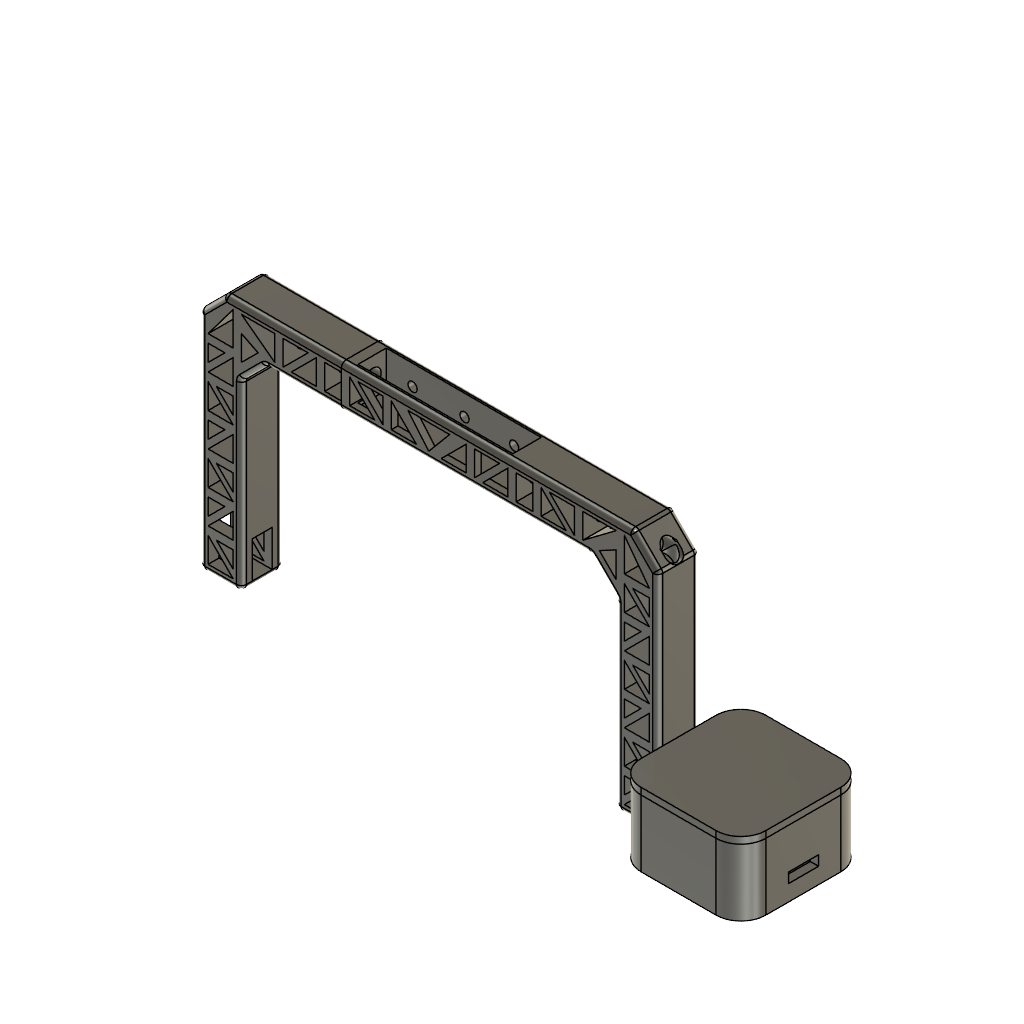
Gaslands Gate (Autodesk Fusion 360 design; units mm, degrees)
Autodesk Fusion 360 part; units mm, degrees
sketch "Sketch1" plane through (0, 0, 0) normal (0, 1, 0) x (1, 0, 0)
  line L0 (0, 0) -> (25, 0)
  line L1 (25, 0) -> (25, -125)
  line L2 (25, -125) -> (250, -125)
  line L3 (250, -125) -> (250, 0)
  line L4 (250, 0) -> (275, 0)
  line L5 (275, 0) -> (275, -150)
  line L6 (275, -150) -> (0, -150)
  line L7 (0, -150) -> (0, 0)
  line L8 (25, -110) -> (40, -125)
  line L9 (250, -110) -> (235, -125)
  line L10 (275, -135) -> (260, -150)
  line L11 (0, -135) -> (15, -150)
  dimension "d1" = 25
  constraint coincident L0.start L7.end
  constraint horizontal L0
  constraint perpendicular L0 L1
  constraint perpendicular L1 L2
  constraint perpendicular L2 L3
  constraint perpendicular L1 L4
  constraint perpendicular L4 L5
  constraint perpendicular L5 L6
  constraint perpendicular L0 L7
  constraint coincident L1 L8.start
  constraint coincident L2 L8.end
  constraint coincident L3 L9.start
  constraint coincident L2 L9.end
  constraint perpendicular L8 L9
  constraint coincident L5 L10.start
  constraint coincident L6 L10.end
  constraint parallel L9 L10
  constraint coincident L7 L11.start
  constraint coincident L6 L11.end
  constraint perpendicular L10 L11
  measures "d1" distance of L3.end L4.end
extrude "Extrude1" add sketch "Sketch1" along normal blind 25 contours L0 L1 L2 L3 L4 L5 L6 L7 L10 L11 | L1 L2 L8 | L2 L3 L9 makes body 1
fillet "Fillet1" radius 3 28 edges at (0, 12.5, 135) (32.5, 25, 117.5) (250, 0, 55) (137.5, 0, 150) (235, 12.5, 125) (250, 12.5, 110) (0, 0, 67.5) (137.5, 0, 125) (25, 25, 55) (40, 12.5, 125) (250, 25, 55) (242.5, 25, 117.5) (137.5, 25, 150) (275, 0, 67.5) (260, 12.5, 150) (242.5, 0, 117.5) (7.5, 0, 142.5) (0, 25, 67.5) (267.5, 25, 142.5) (275, 25, 67.5) (275, 12.5, 135) (25, 0, 55) (32.5, 0, 117.5) (25, 12.5, 110) (267.5, 0, 142.5) (137.5, 25, 125) (7.5, 25, 142.5) (15, 12.5, 150) 12 faces at (170, 0, 141.6667) (250, 8.3333, 73.3333) (170, 25, 141.6667) (275, 8.3333, 45) (0, 8.3333, 90) (178.3333, 16.6667, 150) (270, 8.3333, 140) (5, 8.3333, 140) (105, 8.3333, 125) (245, 8.3333, 115) (25, 8.3333, 36.6667) (30, 8.3333, 115) on bodies 1
sketch "Sketch2" plane through (0, 0, 150) normal (0, 0, 1) x (-1, 0, 0)
  line L0 (-16.2426, -3) -> (-258.7574, -3)
  line L1 (-258.7574, -3) -> (-258.7574, -22)
  line L2 (-258.7574, -22) -> (-16.2426, -22)
  line L3 (-16.2426, -22) -> (-16.2426, -3)
  line L4 (-275, -50, -150) -> (-350, -50, -150)
  line L5 (-350, -50, -150) -> (-350, 25, -150)
  line L6 (-350, 25, -150) -> (-275, 25, -150)
  line L7 (-275, 25, -150) -> (-275, -50, -150)
extrude "Extrude2" add sketch "Sketch2" along normal blind 40 separate body contours L4 L5 L6 L7 in plane through (0, 0, 0) normal (0, 0, 1) makes body 2
sketch "Sketch3" plane through (0, 0, 40) normal (0, 0, 1) x (-1, 0, 0)
  line L0 (-275, 25) -> (-350, 25)
  line L1 (-350, 25) -> (-350, -50)
  line L2 (-350, -50) -> (-275, -50)
  line L3 (-275, -50) -> (-275, 25)
  line L4 (-280, -45) -> (-345, -45)
  line L5 (-345, -45) -> (-345, 20)
  line L6 (-345, 20) -> (-280, 20)
  line L7 (-280, 20) -> (-280, -45)
  constraint horizontal L4
  constraint vertical L5
  constraint horizontal L6
  constraint vertical L7
extrude "Extrude3" cut sketch "Sketch3" against normal blind 35 contours L4 L5 L6 L7 bodies 2 1
fillet "Fillet2" radius 15 8 edges at (280, 45, 22.5) (275, -25, 20) (350, -25, 20) (350, 50, 20) (345, -20, 22.5) (345, 45, 22.5) (280, -20, 22.5) (275, 50, 20) on bodies 2
sketch "Sketch4" plane through (250, 0, 0) normal (-1, 0, 0) x (0, -1, 0)
  line L0 (-3, 3) -> (-3, 108.7574)
  line L1 (-3, 108.7574) -> (-22, 108.7574)
  line L2 (-22, 108.7574) -> (-22, 3)
  line L3 (-22, 3) -> (-3, 3)
sketch "Sketch5" plane through (250, 0, 0) normal (-1, 0, 0) x (0, -1, 0)
  line L0 (-22, 7) -> (-18.5, 7) construction
  line L1 (-3, 7) -> (-6.5, 7) construction
  line L2 (-18.5, 3.0129) -> (-6.5, 3.0129)
  line L3 (-6.5, 3.0129) -> (-6.5, 25.0129)
  line L4 (-6.5, 25.0129) -> (-18.5, 25.0129)
  line L5 (-18.5, 25.0129) -> (-18.5, 3.0129)
  dimension "d13" = 3.5
  dimension "d14" = 3.5
  dimension "d15" = 12
  dimension "d16" = 22
  constraint horizontal L0
  constraint horizontal L1
  constraint horizontal L2
  constraint vertical L3
  constraint horizontal L4
  constraint vertical L5
  measures "d13" distance of L0.start L0.end
  measures "d14" distance of L1.start L1.end
  measures "d15" distance of L2.start L2.end
  measures "d16" distance of L2.start L4.end
extrude "Extrude4" cut sketch "Sketch5" against normal blind 50 bodies 2 1
sketch "Sketch6" plane through (25, 0, 0) normal (1, 0, 0) x (0, 1, 0)
  line L0 (3, 108.7574) -> (3, 3)
  line L1 (3, 3) -> (22, 3)
  line L2 (22, 3) -> (22, 108.7574)
  line L3 (22, 108.7574) -> (3, 108.7574)
  line L4 (3, 10) -> (6.5, 10) construction
  line L5 (22, 10) -> (18.5, 10) construction
  line L6 (6.5, 3) -> (18.5, 3)
  line L7 (18.5, 3) -> (18.5, 25)
  line L8 (18.5, 25) -> (6.5, 25)
  line L9 (6.5, 25) -> (6.5, 3)
  dimension "d19" = 3.5
  dimension "d20" = 3.5
  dimension "d21" = 12
  dimension "d22" = 22
  constraint coincident L0 L4.start
  constraint perpendicular L0 L4
  constraint coincident L2 L5.start
  constraint perpendicular L2 L5
  constraint horizontal L6
  constraint vertical L7
  constraint horizontal L8
  constraint vertical L9
  constraint coincident L1 L6.start
  measures "d19" distance of L4.start L4.end
  measures "d20" distance of L5.start L5.end
  measures "d21" distance of L6.start L6.end
  measures "d22" distance of L6.start L8.end
extrude "Extrude5" cut sketch "Sketch6" against normal blind 50 contours L1 L6 L7 L8 L9 bodies 1 2
sketch "Sketch7" plane through (0, 0, 150) normal (0, 0, 1) x (-1, 0, 0)
  line L0 (-16.2426, -3) -> (-258.7574, -3)
  line L1 (-258.7574, -3) -> (-258.7574, -22)
  line L2 (-258.7574, -22) -> (-16.2426, -22)
  line L3 (-16.2426, -22) -> (-16.2426, -3)
  line L4 (-16.2426, -12.5) -> (-91.2426, -12.5) construction
  line L5 (-258.7574, -12.5) -> (-183.7574, -12.5) construction
  line L6 (-184, -4) -> (-91, -4)
  line L7 (-91, -4) -> (-91, -21)
  line L8 (-91, -21) -> (-184, -21)
  line L9 (-184, -21) -> (-184, -4)
  dimension "d25" = 75
  dimension "d26" = 75
  constraint midpoint L3 L4.start
  constraint perpendicular L1 L4
  constraint midpoint L1 L5.start
  constraint perpendicular L1 L5
  constraint horizontal L6
  constraint vertical L7
  constraint horizontal L8
  constraint vertical L9
  measures "d25" distance of L4.start L4.end
  measures "d26" distance of L5.start L5.end
extrude "Extrude6" cut sketch "Sketch7" against normal blind 22 contours L6 L7 L8 L9 bodies 2 1
sketch "Sketch9" plane through (0, 21, 0) normal (0, -1, 0) x (1, 0, 0)
  line L0 (184, 150) -> (91, 150)
  line L1 (91, 150) -> (91, 128)
  line L2 (91, 128) -> (184, 128)
  line L3 (184, 128) -> (184, 150)
  circle A0 centre (137.9868, 137.5616) radius 2.75
  circle A1 centre (167.7904, 137.5616) radius 2.75
  circle A2 centre (106.797, 137.7349) radius 2.75
  dimension "d34" = 5.5
  dimension "d35" = 5.5
  dimension "d36" = 5.5
  measures "d34" diameter of A0
  measures "d35" diameter of A1
  measures "d36" diameter of A2
sketch "Sketch11" plane through (350, 0, 0) normal (1, 0, 0) x (0, 1, 0)
  line L0 (35, 0) -> (35, 40)
  line L1 (35, 40) -> (-10, 40)
  line L2 (-10, 40) -> (-10, 0)
  line L3 (-10, 0) -> (35, 0)
  line L4 (3.6168, 9.6364) -> (21.6168, 9.6364)
  line L5 (21.6168, 9.6364) -> (21.6168, 15.6364)
  line L6 (21.6168, 15.6364) -> (3.6168, 15.6364)
  line L7 (3.6168, 15.6364) -> (3.6168, 9.6364)
  dimension "d30" = 18
  dimension "d31" = 6
  constraint horizontal L4
  constraint vertical L5
  constraint horizontal L6
  constraint vertical L7
  measures "d30" distance of L4.start L4.end
  measures "d31" distance of L4.start L6.end
extrude "Extrude7" cut sketch "Sketch11" against normal blind 48 contours L4 L5 L6 L7 bodies 1 2
extrude "Extrude8" cut sketch "Sketch9" against normal blind 4 contours A0 | A1 | A2 bodies 1 2
hole "Hole1" at (184, 12.5, 139) direction (1, 0, 0) diameter 10 depth 104 tip angle 118 bodies 1 2
hole "Hole2" at (91, 12.9327, 138.6221) direction (-1, 0, 0) diameter 10 depth 95 tip angle 118 bodies 1 2
hole "Hole3" at (-2.2469, 12.2437, 25) direction (0, 0, 1) diameter 10 depth 145 tip angle 118 bodies 1
hole "Hole4" at (268.4842, 12.4358, 25.0129) direction (0, 0, 1) diameter 10 depth 116 tip angle 118 bodies 2 1
sketch "Sketch13" plane through (0, 0, 40) normal (0, 0, 1) x (-1, 0, 0)
  line L0 (-345, -30) -> (-345, 5)
  arc A0 (-330, 20) -> (-345, 5) centre (-330, 5) ccw
  line L1 (-330, 20) -> (-295, 20)
  arc A1 (-280, 5) -> (-295, 20) centre (-295, 5) ccw
  line L2 (-280, 5) -> (-280, -30)
  arc A2 (-295, -45) -> (-280, -30) centre (-295, -30) ccw
  line L3 (-295, -45) -> (-330, -45)
  arc A3 (-345, -30) -> (-330, -45) centre (-330, -30) ccw
  arc A4 (-290, -50) -> (-275, -35) centre (-290, -35) ccw
  line L4 (-275, -35) -> (-275, 10)
  arc A5 (-275, 10) -> (-290, 25) centre (-290, 10) ccw
  line L5 (-290, 25) -> (-335, 25)
  arc A6 (-335, 25) -> (-350, 10) centre (-335, 10) ccw
  line L6 (-350, 10) -> (-350, -35)
  arc A7 (-350, -35) -> (-335, -50) centre (-335, -35) ccw
  line L7 (-335, -50) -> (-290, -50)
  line L8 (-350, -50) -> (-275, -50)
  line L9 (-275, -50) -> (-275, 25)
  line L10 (-275, 25) -> (-350, 25)
  line L11 (-350, 25) -> (-350, -50)
  constraint horizontal L8
  constraint vertical L9
  constraint horizontal L10
  constraint vertical L11
extrude "Extrude9" add sketch "Sketch13" along normal blind 4 separate body contours L0 A0 L1 A1 L2 A2 L3 A3 | A4 L4 A5 L5 A6 L6 A7 L7 L8 L9 L10 L11 makes body 3
sketch "Sketch14" plane through (0, 0, 0) normal (0, -1, 0) x (1, 0, 0)
  line L0 (3, 133.7574) -> (3, 3)
  line L1 (3, 3) -> (22, 3)
  line L2 (22, 3) -> (22, 108.7574)
  arc A0 (23.7574, 113) -> (22, 108.7574) centre (28, 108.7574) ccw
  line L3 (23.7574, 113) -> (37, 126.2426)
  arc A1 (41.2426, 128) -> (37, 126.2426) centre (41.2426, 122) ccw
  line L4 (41.2426, 128) -> (233.7574, 128)
  arc A2 (238, 126.2426) -> (233.7574, 128) centre (233.7574, 122) ccw
  line L5 (238, 126.2426) -> (251.2426, 113)
  arc A3 (253, 108.7574) -> (251.2426, 113) centre (247, 108.7574) ccw
  line L6 (253, 108.7574) -> (253, 3)
  line L7 (253, 3) -> (272, 3)
  line L8 (272, 3) -> (272, 133.7574)
  line L9 (272, 133.7574) -> (258.7574, 147)
  line L10 (258.7574, 147) -> (16.2426, 147)
  line L11 (16.2426, 147) -> (3, 133.7574)
  line L12 (5, 5) -> (20, 5)
  line L13 (20, 5) -> (5, 20)
  line L14 (5, 20) -> (5, 5)
  line L15 (20, 10) -> (10, 20)
  line L16 (10, 20) -> (20, 20)
  line L17 (20, 10) -> (20, 20)
  line L18 (5, 25) -> (20, 25)
  line L19 (20, 25) -> (20, 40)
  line L20 (20, 40) -> (5, 25)
  line L21 (5, 30) -> (15, 40)
  line L22 (15, 40) -> (5, 40)
  line L23 (5, 40) -> (5, 30)
  line L24 (20, 45) -> (5, 45)
  line L25 (5, 45) -> (5, 60)
  line L26 (5, 60) -> (20, 45)
  line L27 (20, 50) -> (10, 60)
  line L28 (10, 60) -> (20, 60)
  line L29 (20, 60) -> (20, 50)
  line L30 (5, 65) -> (20, 65)
  line L31 (20, 65) -> (20, 80)
  line L32 (20, 80) -> (5, 65)
  line L33 (5, 80) -> (5, 70)
  line L34 (5, 70) -> (15, 80)
  line L35 (15, 80) -> (5, 80)
  line L36 (5, 85) -> (20, 85)
  line L37 (20, 85) -> (5, 100)
  line L38 (5, 100) -> (5, 85)
  line L39 (10, 100) -> (20, 90)
  line L40 (20, 90) -> (20, 100)
  line L41 (20, 100) -> (10, 100)
  line L42 (5, 105) -> (20, 105)
  line L43 (20, 105) -> (20, 120)
  line L44 (20, 120) -> (5, 105)
  line L45 (5, 110) -> (15, 120)
  line L46 (15, 120) -> (5, 120)
  line L47 (5, 120) -> (5, 110)
  line L48 (255, 5) -> (270, 5)
  line L49 (270, 5) -> (270, 20)
  line L50 (270, 20) -> (255, 5)
  line L51 (255, 10) -> (265, 20)
  line L52 (265, 20) -> (255, 20)
  line L53 (255, 20) -> (255, 10)
  line L54 (270, 25) -> (255, 25)
  line L55 (255, 25) -> (255, 40)
  line L56 (255, 40) -> (270, 25)
  line L57 (270, 30) -> (260, 40)
  line L58 (260, 40) -> (270, 40)
  line L59 (270, 40) -> (270, 30)
  line L60 (255, 45) -> (270, 45)
  line L61 (270, 45) -> (270, 60)
  line L62 (270, 60) -> (255, 45)
  line L63 (255, 50) -> (265, 60)
  line L64 (265, 60) -> (255, 60)
  line L65 (255, 60) -> (255, 50)
  line L66 (255, 65) -> (270, 65)
  line L67 (270, 65) -> (255, 80)
  line L68 (255, 80) -> (255, 65)
  line L69 (260, 80) -> (270, 70)
  line L70 (270, 70) -> (270, 80)
  line L71 (270, 80) -> (260, 80)
  line L72 (270, 85) -> (255, 85)
  line L73 (255, 85) -> (270, 100)
  line L74 (270, 100) -> (270, 85)
  line L75 (255, 90) -> (265, 100)
  line L76 (255, 90) -> (255, 100)
  line L77 (255, 100) -> (265, 100)
  line L78 (270, 105) -> (255, 105)
  line L79 (255, 105) -> (255, 120)
  line L80 (255, 120) -> (270, 105)
  line L81 (270, 110) -> (270, 120)
  line L82 (270, 120) -> (260, 120)
  line L83 (260, 120) -> (270, 110)
  line L84 (5, 125) -> (20, 145)
  line L85 (20, 145) -> (20, 125)
  line L86 (20, 125) -> (5, 125)
  line L87 (25, 120) -> (35, 130)
  line L88 (35, 130) -> (25, 135)
  line L89 (25, 135) -> (25, 120)
  line L90 (25, 145) -> (45, 145)
  line L91 (45, 145) -> (45, 130)
  line L92 (45, 130) -> (25, 145)
  line L93 (270, 125) -> (255, 125)
  line L94 (255, 125) -> (255, 145)
  line L95 (255, 145) -> (270, 125)
  line L96 (250, 145) -> (230, 130)
  line L97 (230, 130) -> (230, 145)
  line L98 (230, 145) -> (250, 145)
  line L99 (250, 135) -> (250, 119.6213)
  line L100 (250, 119.6213) -> (240, 129.6213)
  line L101 (240, 129.6213) -> (250, 135)
  line L102 (225, 130) -> (210, 145)
  line L103 (210, 145) -> (225, 145)
  line L104 (225, 145) -> (225, 130)
  line L105 (205, 145) -> (220, 130)
  line L106 (220, 130) -> (205, 130)
  line L107 (205, 130) -> (205, 145)
  line L108 (50, 145) -> (50, 130)
  line L109 (50, 130) -> (65, 145)
  line L110 (65, 145) -> (50, 145)
  line L111 (55, 130) -> (70, 145)
  line L112 (70, 145) -> (70, 130)
  line L113 (70, 130) -> (55, 130)
  line L114 (75, 145) -> (75, 130)
  line L115 (75, 130) -> (85, 130)
  line L116 (85, 130) -> (85, 145)
  line L117 (85, 145) -> (75, 145)
  line L118 (200, 130) -> (200, 145)
  line L119 (200, 145) -> (190, 145)
  line L120 (190, 145) -> (190, 130)
  line L121 (190, 130) -> (200, 130)
  constraint perpendicular L2 L12
  constraint perpendicular L12 L14
  constraint parallel L13 L15
  constraint perpendicular L2 L16
  constraint perpendicular L16 L17
  constraint perpendicular L2 L18
  constraint perpendicular L18 L19
  constraint parallel L20 L21
  constraint parallel L18 L22
  constraint perpendicular L22 L23
  constraint perpendicular L23 L24
  constraint perpendicular L24 L25
  constraint perpendicular L2 L28
  constraint perpendicular L24 L29
  constraint perpendicular L29 L30
  constraint perpendicular L30 L31
  constraint perpendicular L30 L33
  constraint parallel L32 L34
  constraint perpendicular L33 L35
  constraint parallel L35 L36
  constraint perpendicular L32 L37
  constraint perpendicular L36 L38
  constraint parallel L37 L39
  constraint parallel L38 L40
  constraint perpendicular L40 L41
  constraint perpendicular L40 L42
  constraint perpendicular L42 L43
  constraint parallel L44 L45
  constraint parallel L42 L46
  constraint perpendicular L46 L47
  constraint perpendicular L8 L48
  constraint perpendicular L48 L49
  constraint parallel L50 L51
  constraint parallel L48 L52
  constraint perpendicular L52 L53
  constraint perpendicular L49 L54
  constraint perpendicular L54 L55
  constraint parallel L56 L57
  constraint parallel L54 L58
  constraint perpendicular L58 L59
  constraint perpendicular L59 L60
  constraint perpendicular L58 L61
  constraint parallel L62 L63
  constraint perpendicular L6 L64
  constraint perpendicular L64 L65
  constraint perpendicular L65 L66
  constraint perpendicular L66 L68
  constraint parallel L67 L69
  constraint parallel L8 L70
  constraint perpendicular L70 L71
  constraint perpendicular L8 L72
  constraint perpendicular L72 L74
  constraint parallel L73 L75
  constraint vertical L76
  constraint perpendicular L76 L77
  constraint parallel L77 L78
  constraint perpendicular L78 L79
  constraint perpendicular L78 L81
  constraint perpendicular L81 L82
  constraint parallel L80 L83
  constraint perpendicular L10 L85
  constraint perpendicular L85 L86
  constraint parallel L85 L89
  constraint perpendicular L89 L90
  constraint perpendicular L90 L91
  constraint perpendicular L8 L93
  constraint perpendicular L93 L94
  constraint perpendicular L95 L96
  constraint parallel L94 L97
  constraint perpendicular L94 L98
  constraint perpendicular L98 L99
  constraint parallel L5 L100
  constraint parallel L100 L102
  constraint parallel L4 L103
  constraint perpendicular L103 L104
  constraint parallel L4 L106
  constraint perpendicular L4 L107
  constraint perpendicular L90 L108
  constraint perpendicular L108 L110
  constraint parallel L109 L111
  constraint perpendicular L10 L112
  constraint perpendicular L112 L113
  constraint perpendicular L113 L114
  constraint perpendicular L114 L115
  constraint perpendicular L115 L116
  constraint perpendicular L114 L117
  constraint perpendicular L10 L118
  constraint perpendicular L118 L119
  constraint perpendicular L119 L120
  constraint perpendicular L118 L121
extrude "Extrude10" cut sketch "Sketch14" against normal blind 70 contours L12 L13 L14 | L15 L16 L17 | L18 L19 L20 | L21 L22 L23 | L24 L25 L26 | L27 L28 L29 | L30 L31 L32 | L33 L34 L35 | L36 L37 L38 | L39 L40 L41 | L42 L43 L44 | L45 L46 L47 | L48 L49 L50 | L51 L52 L53 | L54 L55 L56 | L57 L58 L59 | L60 L61 L62 | L63 L64 L65 | L66 L67 L68 | L69 L70 L71 | L72 L73 L74 | L75 L76 L77 | L78 L79 L80 | L81 L82 L83 | L84 L85 L86 | L87 L88 L89 | L90 L91 L92 | L93 L94 L95 | L96 L97 L98 | L99 L100 L101 | L102 L103 L104 | L105 L106 L107 | L108 L109 L110 | L111 L112 L113 | L114 L115 L116 L117 | L118 L119 L120 L121 bodies 1
sketch "Sketch15" plane through (0, 0, 0) normal (0, -1, 0) x (1, 0, 0)
  line L0 (3, 133.7574) -> (3, 3)
  line L1 (3, 3) -> (22, 3)
  line L2 (22, 3) -> (22, 108.7574)
  arc A0 (23.7574, 113) -> (22, 108.7574) centre (28, 108.7574) ccw
  line L3 (23.7574, 113) -> (37, 126.2426)
  arc A1 (41.2426, 128) -> (37, 126.2426) centre (41.2426, 122) ccw
  line L4 (41.2426, 128) -> (233.7574, 128)
  arc A2 (238, 126.2426) -> (233.7574, 128) centre (233.7574, 122) ccw
  line L5 (238, 126.2426) -> (251.2426, 113)
  arc A3 (253, 108.7574) -> (251.2426, 113) centre (247, 108.7574) ccw
  line L6 (253, 108.7574) -> (253, 3)
  line L7 (253, 3) -> (272, 3)
  line L8 (272, 3) -> (272, 133.7574)
  line L9 (272, 133.7574) -> (258.7574, 147)
  line L10 (258.7574, 147) -> (16.2426, 147)
  line L11 (16.2426, 147) -> (3, 133.7574)
  line L12 (270, 5) -> (255, 5)
  line L13 (255, 5) -> (270, 20)
  line L14 (270, 20) -> (270, 5)
  line L15 (270, 45) -> (255, 45)
  line L16 (255, 45) -> (270, 60)
  line L17 (270, 60) -> (270, 45)
  line L18 (270, 85) -> (255, 85)
  line L19 (255, 85) -> (270, 100)
  line L20 (270, 100) -> (270, 85)
  line L21 (270, 125) -> (255, 125)
  line L22 (255, 125) -> (255, 145)
  line L23 (255, 145) -> (270, 125)
  line L24 (205, 145) -> (220, 130)
  line L25 (220, 130) -> (205, 130)
  line L26 (205, 130) -> (205, 145)
  line L27 (50, 130) -> (50, 145)
  line L28 (50, 145) -> (65, 145)
  line L29 (65, 145) -> (50, 130)
  line L30 (15, 120) -> (5, 110)
  line L31 (5, 110) -> (5, 120)
  line L32 (5, 120) -> (15, 120)
  line L33 (5, 70) -> (5, 80)
  line L34 (5, 80) -> (15, 80)
  line L35 (15, 80) -> (5, 70)
  line L36 (15, 40) -> (5, 30)
  line L37 (5, 30) -> (5, 40)
  line L38 (5, 40) -> (15, 40)
  line L39 (20, 5) -> (5, 5)
  line L40 (5, 5) -> (5, 20)
  line L41 (5, 20) -> (20, 5)
  line L42 (20, 45) -> (5, 45)
  line L43 (5, 45) -> (5, 60)
  line L44 (5, 60) -> (20, 45)
  line L45 (20, 85) -> (5, 85)
  line L46 (5, 85) -> (5, 100)
  line L47 (5, 100) -> (20, 85)
  line L48 (5, 125) -> (20, 145)
  line L49 (20, 145) -> (20, 125)
  line L50 (20, 125) -> (5, 125)
  line L51 (55, 130) -> (70, 145)
  line L52 (70, 145) -> (70, 130)
  line L53 (70, 130) -> (55, 130)
  line L54 (225, 130) -> (210, 145)
  line L55 (210, 145) -> (225, 145)
  line L56 (225, 145) -> (225, 130)
  line L57 (270, 120) -> (270, 110)
  line L58 (270, 110) -> (260, 120)
  line L59 (260, 120) -> (270, 120)
  line L60 (270, 70) -> (260, 80)
  line L61 (260, 80) -> (270, 80)
  line L62 (270, 80) -> (270, 70)
  line L63 (270, 25) -> (255, 25)
  line L64 (255, 25) -> (255, 40)
  line L65 (255, 40) -> (270, 25)
  line L66 (265, 20) -> (255, 10)
  line L67 (255, 10) -> (255, 20)
  line L68 (255, 20) -> (265, 20)
  line L69 (265, 60) -> (255, 50)
  line L70 (255, 50) -> (255, 60)
  line L71 (255, 60) -> (265, 60)
  line L72 (255, 100) -> (265, 100)
  line L73 (265, 100) -> (255, 90)
  line L74 (255, 90) -> (255, 100)
  line L75 (250, 135) -> (250, 119.6213)
  line L76 (250, 119.6213) -> (240, 129.6213)
  line L77 (240, 129.6213) -> (250, 135)
  line L78 (200, 145) -> (200, 130)
  line L79 (200, 130) -> (190, 130)
  line L80 (190, 130) -> (190, 145)
  line L81 (190, 145) -> (200, 145)
  line L82 (25, 145) -> (45, 145)
  line L83 (45, 145) -> (45, 130)
  line L84 (45, 130) -> (25, 145)
  line L85 (20, 105) -> (5, 105)
  line L86 (5, 105) -> (20, 120)
  line L87 (20, 120) -> (20, 105)
  line L88 (20, 50) -> (10, 60)
  line L89 (10, 60) -> (20, 60)
  line L90 (20, 60) -> (20, 50)
  line L91 (20, 25) -> (5, 25)
  line L92 (5, 25) -> (20, 40)
  line L93 (20, 40) -> (20, 25)
  line L94 (20, 20) -> (20, 10)
  line L95 (20, 10) -> (10, 20)
  line L96 (10, 20) -> (20, 20)
  line L97 (20, 65) -> (5, 65)
  line L98 (5, 65) -> (20, 80)
  line L99 (20, 80) -> (20, 65)
  line L100 (20, 90) -> (10, 100)
  line L101 (10, 100) -> (20, 100)
  line L102 (20, 100) -> (20, 90)
  line L103 (35, 130) -> (25, 120)
  line L104 (25, 120) -> (25, 135)
  line L105 (25, 135) -> (35, 130)
  line L106 (75, 130) -> (75, 145)
  line L107 (75, 145) -> (85, 145)
  line L108 (85, 145) -> (85, 130)
  line L109 (85, 130) -> (75, 130)
  line L110 (250, 145) -> (230, 130)
  line L111 (230, 130) -> (230, 145)
  line L112 (230, 145) -> (250, 145)
  line L113 (270, 105) -> (255, 105)
  line L114 (255, 105) -> (255, 120)
  line L115 (255, 120) -> (270, 105)
  line L116 (270, 65) -> (255, 65)
  line L117 (255, 65) -> (255, 80)
  line L118 (255, 80) -> (270, 65)
  line L119 (270, 30) -> (260, 40)
  line L120 (260, 40) -> (270, 40)
  line L121 (270, 40) -> (270, 30)
  line L122 (90, 145) -> (90, 130)
  line L123 (90, 130) -> (105, 130)
  line L124 (105, 130) -> (90, 145)
  line L125 (95, 145) -> (110, 130)
  line L126 (110, 130) -> (110, 145)
  line L127 (110, 145) -> (95, 145)
  line L128 (185, 130) -> (185, 145)
  line L129 (185, 145) -> (170, 130)
  line L130 (170, 130) -> (185, 130)
  line L131 (180, 145) -> (165, 130)
  line L132 (165, 130) -> (165, 145)
  line L133 (165, 145) -> (180, 145)
  line L134 (160, 130) -> (145, 130)
  line L135 (145, 130) -> (160, 145)
  line L136 (160, 145) -> (160, 130)
  line L137 (115, 145) -> (115, 130)
  line L138 (115, 130) -> (130, 130)
  line L139 (130, 130) -> (115, 145)
  line L140 (125, 145) -> (150, 145)
  line L141 (150, 145) -> (137.5, 130.0397)
  line L142 (137.5, 130.0397) -> (125, 145)
  constraint perpendicular L10 L122
  constraint perpendicular L122 L123
  constraint parallel L124 L125
  constraint parallel L122 L126
  constraint perpendicular L126 L127
  constraint perpendicular L4 L128
  constraint perpendicular L125 L129
  constraint perpendicular L128 L130
  constraint vertical L132
  constraint perpendicular L132 L133
  constraint perpendicular L132 L134
  constraint parallel L131 L135
  constraint perpendicular L134 L136
  constraint vertical L137
  constraint perpendicular L137 L138
  constraint parallel L4 L140
extrude "Extrude11" cut sketch "Sketch15" against normal blind 10 contours L122 L123 L124 | L125 L126 L127 | L128 L129 L130 | L131 L132 L133 | L134 L135 L136 | L137 L138 L139 | L140 L141 L142 bodies 1
sketch "Sketch16" plane through (0, 50, 0) normal (0, 1, 0) x (-1, 0, 0)
  line L0 (-290, 0) -> (-290, 40)
  line L1 (-290, 40) -> (-335, 40)
  line L2 (-335, 40) -> (-335, 0)
  line L3 (-335, 0) -> (-290, 0)
  circle A0 centre (-300, 20) radius 6.5
  line L4 (-328, 15) -> (-314.2, 15)
  line L5 (-314.2, 15) -> (-314.2, 24.7)
  line L6 (-314.2, 24.7) -> (-328, 24.7)
  line L7 (-328, 24.7) -> (-328, 15)
  dimension "d57" = 13
  dimension "d58" = 13.8
  dimension "d59" = 9.7
  constraint horizontal L4
  constraint vertical L5
  constraint horizontal L6
  constraint vertical L7
  measures "d57" diameter of A0
  measures "d58" distance of L4.start L4.end
  measures "d59" distance of L4.start L6.end
extrude "Extrude12" cut sketch "Sketch16" against normal blind 19 contours A0 | L4 L5 L6 L7 bodies 2
ref_plane "WorkPlane1" through (85, 12.5, 137.5) normal (-1, 0, 0) x (0, 0, 1)
split "Split1" by plane through (85, 12.5, 137.5) normal (-1, 0, 0) bodies 1 makes body 4 at (9.3333, 0, 134.5858)
